Autodesk Fusion 360 part; units mm, degrees
(part 2 of 3)
sketch "Control PCB carrier sketch" plane through (0, 0, 46.5) normal (0, 0, 1) x (1, 0, 0) in component "V2 control PCB removable carrier"
  line L0 (42, 28) -> (98, 28)
  line L1 (100, 30) -> (100, 61)
  line L2 (98, 63) -> (42, 63)
  line L3 (40, 61) -> (40, 30)
  arc A0 (98, 28) -> (100, 30) centre (98, 30) ccw
  arc A1 (100, 61) -> (98, 63) centre (98, 61) ccw
  arc A2 (42, 63) -> (40, 61) centre (42, 61) ccw
  arc A3 (40, 30) -> (42, 28) centre (42, 30) ccw
extrude "Control PCB carrier" add sketch "Control PCB carrier sketch" along normal blind 2.5 separate body makes body 8 in component "V2 control PCB removable carrier"
ref_plane "WorkPlane2" through (0, 0, 46.4) normal (0, 0, 1) x (1, 0, 0) in component "V2 control PCB removable carrier"
sketch "Carrier M3 through sketch" plane through (0, 0, 46.4) normal (0, 0, 1) x (1, 0, 0) in component "V2 control PCB removable carrier"
  circle A0 centre (45, 44) radius 1.7
  circle A1 centre (95, 44) radius 1.7
extrude "Carrier M3 through" cut sketch "Carrier M3 through sketch" along normal blind 2.8 bodies 8 in component "V2 control PCB removable carrier"
ref_plane "WorkPlane3" through (0, 0, 49) normal (0, 0, 1) x (1, 0, 0) in component "V2 control PCB removable carrier"
sketch "Control PCB corner support pads" plane through (0, 0, 49) normal (0, 0, 1) x (1, 0, 0) in component "V2 control PCB removable carrier"
  line L0 (54, 30) -> (57, 30)
  line L1 (57, 30) -> (57, 33)
  line L2 (57, 33) -> (54, 33)
  line L3 (54, 33) -> (54, 30)
  line L4 (54, 57) -> (57, 57)
  line L5 (57, 57) -> (57, 60)
  line L6 (57, 60) -> (54, 60)
  line L7 (54, 60) -> (54, 57)
  line L8 (83, 30) -> (86, 30)
  line L9 (86, 30) -> (86, 33)
  line L10 (86, 33) -> (83, 33)
  line L11 (83, 33) -> (83, 30)
  line L12 (83, 57) -> (86, 57)
  line L13 (86, 57) -> (86, 60)
  line L14 (86, 60) -> (83, 60)
  line L15 (83, 60) -> (83, 57)
extrude "PCB stand-off pads" add sketch "Control PCB corner support pads" along normal blind 4 bodies 8 in component "V2 control PCB removable carrier"
ref_plane "WorkPlane4" through (0, 0, 49) normal (0, 0, 1) x (1, 0, 0) in component "V2 control PCB removable carrier"
sketch "Control PCB guide sketch" plane through (0, 0, 49) normal (0, 0, 1) x (1, 0, 0) in component "V2 control PCB removable carrier"
  line L0 (51.5, 30) -> (53.5, 30)
  line L1 (53.5, 30) -> (53.5, 60)
  line L2 (53.5, 60) -> (51.5, 60)
  line L3 (51.5, 60) -> (51.5, 30)
extrude "Control PCB guide" add sketch "Control PCB guide sketch" along normal blind 5 bodies 8 in component "V2 control PCB removable carrier"
ref_plane "WorkPlane5" through (0, 0, 49) normal (0, 0, 1) x (1, 0, 0) in component "V2 control PCB removable carrier"
sketch "Control PCB guide sketch (1)" plane through (0, 0, 49) normal (0, 0, 1) x (1, 0, 0) in component "V2 control PCB removable carrier"
  line L0 (86.5, 30) -> (88.5, 30)
  line L1 (88.5, 30) -> (88.5, 60)
  line L2 (88.5, 60) -> (86.5, 60)
  line L3 (86.5, 60) -> (86.5, 30)
extrude "Control PCB guide (1)" add sketch "Control PCB guide sketch (1)" along normal blind 5 bodies 8 in component "V2 control PCB removable carrier"
ref_plane "WorkPlane6" through (0, 0, 49) normal (0, 0, 1) x (1, 0, 0) in component "V2 control PCB removable carrier"
sketch "Control PCB guide sketch (2)" plane through (0, 0, 49) normal (0, 0, 1) x (1, 0, 0) in component "V2 control PCB removable carrier"
  line L0 (54, 27.5) -> (86, 27.5)
  line L1 (86, 27.5) -> (86, 29.5)
  line L2 (86, 29.5) -> (54, 29.5)
  line L3 (54, 29.5) -> (54, 27.5)
extrude "Control PCB guide (2)" add sketch "Control PCB guide sketch (2)" along normal blind 5 bodies 8 in component "V2 control PCB removable carrier"
ref_plane "WorkPlane7" through (0, 0, 46.4) normal (0, 0, 1) x (1, 0, 0) in component "V2 control PCB removable carrier"
sketch "PCB retaining strap slot sketch" plane through (0, 0, 46.4) normal (0, 0, 1) x (1, 0, 0) in component "V2 control PCB removable carrier"
  line L0 (52, 48) -> (54, 48)
  line L1 (54, 48) -> (54, 54)
  line L2 (54, 54) -> (52, 54)
  line L3 (52, 54) -> (52, 48)
extrude "PCB retaining strap slot" cut sketch "PCB retaining strap slot sketch" along normal blind 2.8 bodies 8 in component "V2 control PCB removable carrier"
ref_plane "WorkPlane8" through (0, 0, 46.4) normal (0, 0, 1) x (1, 0, 0) in component "V2 control PCB removable carrier"
sketch "PCB retaining strap slot sketch (1)" plane through (0, 0, 46.4) normal (0, 0, 1) x (1, 0, 0) in component "V2 control PCB removable carrier"
  line L0 (85, 48) -> (87, 48)
  line L1 (87, 48) -> (87, 54)
  line L2 (87, 54) -> (85, 54)
  line L3 (85, 54) -> (85, 48)
extrude "PCB retaining strap slot (1)" cut sketch "PCB retaining strap slot sketch (1)" along normal blind 2.8 bodies 8 in component "V2 control PCB removable carrier"
ref_plane "WorkPlane1" through (0, 0, 58.6) normal (0, 0, 1) x (1, 0, 0) in component "V2 captured tactile plunger 1"
sketch "Tactile contact stem" plane through (0, 0, 58.6) normal (0, 0, 1) x (1, 0, 0) in component "V2 captured tactile plunger 1"
  circle A0 centre (62.38, 53) radius 2
extrude "Tactile contact stem (1)" add sketch "Tactile contact stem" along normal blind 8.2 separate body makes body 9 in component "V2 captured tactile plunger 1"
ref_plane "WorkPlane2" through (0, 0, 65.2) normal (0, 0, 1) x (1, 0, 0) in component "V2 captured tactile plunger 1"
sketch "Captive flange" plane through (0, 0, 65.2) normal (0, 0, 1) x (1, 0, 0) in component "V2 captured tactile plunger 1"
  circle A0 centre (62.38, 53) radius 3.5
extrude "Captive flange (1)" add sketch "Captive flange" along normal blind 1.6 bodies 9 in component "V2 captured tactile plunger 1"
ref_plane "WorkPlane3" through (0, 0, 66.8) normal (0, 0, 1) x (1, 0, 0) in component "V2 captured tactile plunger 1"
sketch "Finger tip" plane through (0, 0, 66.8) normal (0, 0, 1) x (1, 0, 0) in component "V2 captured tactile plunger 1"
  circle A0 centre (62.38, 53) radius 2.75
extrude "Finger tip (1)" add sketch "Finger tip" along normal blind 3.6 bodies 9 in component "V2 captured tactile plunger 1"
ref_plane "WorkPlane1" through (0, 0, 58.6) normal (0, 0, 1) x (1, 0, 0) in component "V2 captured tactile plunger 2"
sketch "Tactile contact stem (2)" plane through (0, 0, 58.6) normal (0, 0, 1) x (1, 0, 0) in component "V2 captured tactile plunger 2"
  circle A0 centre (70, 53) radius 2
extrude "Tactile contact stem (1)'" add sketch "Tactile contact stem (2)" along normal blind 8.2 separate body makes body 10 in component "V2 captured tactile plunger 2"
ref_plane "WorkPlane2" through (0, 0, 65.2) normal (0, 0, 1) x (1, 0, 0) in component "V2 captured tactile plunger 2"
sketch "Captive flange (2)" plane through (0, 0, 65.2) normal (0, 0, 1) x (1, 0, 0) in component "V2 captured tactile plunger 2"
  circle A0 centre (70, 53) radius 3.5
extrude "Captive flange (1)'" add sketch "Captive flange (2)" along normal blind 1.6 bodies 10 in component "V2 captured tactile plunger 2"
ref_plane "WorkPlane3" through (0, 0, 66.8) normal (0, 0, 1) x (1, 0, 0) in component "V2 captured tactile plunger 2"
sketch "Finger tip (2)" plane through (0, 0, 66.8) normal (0, 0, 1) x (1, 0, 0) in component "V2 captured tactile plunger 2"
  circle A0 centre (70, 53) radius 2.75
extrude "Finger tip (1)'" add sketch "Finger tip (2)" along normal blind 3.6 bodies 10 in component "V2 captured tactile plunger 2"
ref_plane "WorkPlane1" through (0, 0, 58.6) normal (0, 0, 1) x (1, 0, 0) in component "V2 captured tactile plunger 3"
sketch "Tactile contact stem (3)" plane through (0, 0, 58.6) normal (0, 0, 1) x (1, 0, 0) in component "V2 captured tactile plunger 3"
  circle A0 centre (77.62, 53) radius 2
extrude "Tactile contact stem (1)''" add sketch "Tactile contact stem (3)" along normal blind 8.2 separate body makes body 11 in component "V2 captured tactile plunger 3"
ref_plane "WorkPlane2" through (0, 0, 65.2) normal (0, 0, 1) x (1, 0, 0) in component "V2 captured tactile plunger 3"
sketch "Captive flange (3)" plane through (0, 0, 65.2) normal (0, 0, 1) x (1, 0, 0) in component "V2 captured tactile plunger 3"
  circle A0 centre (77.62, 53) radius 3.5
extrude "Captive flange (1)''" add sketch "Captive flange (3)" along normal blind 1.6 bodies 11 in component "V2 captured tactile plunger 3"
ref_plane "WorkPlane3" through (0, 0, 66.8) normal (0, 0, 1) x (1, 0, 0) in component "V2 captured tactile plunger 3"
sketch "Finger tip (3)" plane through (0, 0, 66.8) normal (0, 0, 1) x (1, 0, 0) in component "V2 captured tactile plunger 3"
  circle A0 centre (77.62, 53) radius 2.75
extrude "Finger tip (1)''" add sketch "Finger tip (3)" along normal blind 3.6 bodies 11 in component "V2 captured tactile plunger 3"
ref_plane "WorkPlane1" through (0, 0, 8) normal (0, 0, 1) x (1, 0, 0) in component "REF main board 90x80x20 - photo estimate"
sketch "Main PCB sketch" plane through (0, 0, 8) normal (0, 0, 1) x (1, 0, 0) in component "REF main board 90x80x20 - photo estimate"
  line L0 (25, 20) -> (115, 20)
  line L1 (115, 20) -> (115, 100)
  line L2 (115, 100) -> (25, 100)
  line L3 (25, 100) -> (25, 20)
extrude "Main PCB" add sketch "Main PCB sketch" along normal blind 1.6 separate body makes body 12 in component "REF main board 90x80x20 - photo estimate"
ref_plane "WorkPlane2" through (0, 0, 9.6) normal (0, 0, 1) x (1, 0, 0) in component "REF main board 90x80x20 - photo estimate"
sketch "ESP32 reference sketch" plane through (0, 0, 9.6) normal (0, 0, 1) x (1, 0, 0) in component "REF main board 90x80x20 - photo estimate"
  line L0 (68, 38) -> (95, 38)
  line L1 (95, 38) -> (95, 88)
  line L2 (95, 88) -> (68, 88)
  line L3 (68, 88) -> (68, 38)
extrude "ESP32 reference" add sketch "ESP32 reference sketch" along normal blind 12 separate body makes body 13 in component "REF main board 90x80x20 - photo estimate"
ref_plane "WorkPlane3" through (0, 0, 9.6) normal (0, 0, 1) x (1, 0, 0) in component "REF main board 90x80x20 - photo estimate"
sketch "nRF24 reference sketch" plane through (0, 0, 9.6) normal (0, 0, 1) x (1, 0, 0) in component "REF main board 90x80x20 - photo estimate"
  line L0 (33, 75) -> (68, 75)
  line L1 (68, 75) -> (68, 93)
  line L2 (68, 93) -> (33, 93)
  line L3 (33, 93) -> (33, 75)
extrude "nRF24 reference" add sketch "nRF24 reference sketch" along normal blind 10 separate body makes body 14 in component "REF main board 90x80x20 - photo estimate"
ref_plane "WorkPlane4" through (0, 0, 9.6) normal (0, 0, 1) x (1, 0, 0) in component "REF main board 90x80x20 - photo estimate"
sketch "MPU6050 reference sketch" plane through (0, 0, 9.6) normal (0, 0, 1) x (1, 0, 0) in component "REF main board 90x80x20 - photo estimate"
  line L0 (36, 34) -> (57, 34)
  line L1 (57, 34) -> (57, 50)
  line L2 (57, 50) -> (36, 50)
  line L3 (36, 50) -> (36, 34)
extrude "MPU6050 reference" add sketch "MPU6050 reference sketch" along normal blind 6 separate body makes body 15 in component "REF main board 90x80x20 - photo estimate"
ref_plane "WorkPlane5" through (0, 0, 9.6) normal (0, 0, 1) x (1, 0, 0) in component "REF main board 90x80x20 - photo estimate"
sketch "Tallest component 20mm total sketch" plane through (0, 0, 9.6) normal (0, 0, 1) x (1, 0, 0) in component "REF main board 90x80x20 - photo estimate"
  line L0 (62, 22) -> (72, 22)
  line L1 (72, 22) -> (72, 32)
  line L2 (72, 32) -> (62, 32)
  line L3 (62, 32) -> (62, 22)
extrude "Tallest component 20mm total" add sketch "Tallest component 20mm total sketch" along normal blind 18.4 separate body makes body 16 in component "REF main board 90x80x20 - photo estimate"
ref_plane "WorkPlane6" through (0, 0, 11) normal (0, 0, 1) x (1, 0, 0) in component "REF main board 90x80x20 - photo estimate"
sketch "Rocker switch side clearance sketch" plane through (0, 0, 11) normal (0, 0, 1) x (1, 0, 0) in component "REF main board 90x80x20 - photo estimate"
  line L0 (18, 23) -> (25, 23)
  line L1 (25, 23) -> (25, 39)
  line L2 (25, 39) -> (18, 39)
  line L3 (18, 39) -> (18, 23)
extrude "Rocker switch side clearance" add sketch "Rocker switch side clearance sketch" along normal blind 12 separate body makes body 17 in component "REF main board 90x80x20 - photo estimate"
ref_plane "WorkPlane7" through (0, 0, 13) normal (0, 0, 1) x (1, 0, 0) in component "REF main board 90x80x20 - photo estimate"
sketch "SMA connector space sketch" plane through (0, 0, 13) normal (0, 0, 1) x (1, 0, 0) in component "REF main board 90x80x20 - photo estimate"
  line L0 (16, 80) -> (25, 80)
  line L1 (25, 80) -> (25, 86)
  line L2 (25, 86) -> (16, 86)
  line L3 (16, 86) -> (16, 80)
extrude "SMA connector space" add sketch "SMA connector space sketch" along normal blind 6 separate body makes body 18 in component "REF main board 90x80x20 - photo estimate"
ref_plane "WorkPlane1" through (0, 0, 53) normal (0, 0, 1) x (1, 0, 0) in component "REF actual combined buttons LEDs PCB - estimated"
sketch "Control PCB estimated 30x30 sketch" plane through (0, 0, 53) normal (0, 0, 1) x (1, 0, 0) in component "REF actual combined buttons LEDs PCB - estimated"
  line L0 (55, 30) -> (85, 30)
  line L1 (85, 30) -> (85, 60)
  line L2 (85, 60) -> (55, 60)
  line L3 (55, 60) -> (55, 30)
extrude "Control PCB estimated 30x30" add sketch "Control PCB estimated 30x30 sketch" along normal blind 1.6 separate body makes body 19 in component "REF actual combined buttons LEDs PCB - estimated"
ref_plane "WorkPlane2" through (0, 0, 54.6) normal (0, 0, 1) x (1, 0, 0) in component "REF actual combined buttons LEDs PCB - estimated"
sketch "Tactile switch 6x6 sketch" plane through (0, 0, 54.6) normal (0, 0, 1) x (1, 0, 0) in component "REF actual combined buttons LEDs PCB - estimated"
  line L0 (59.38, 50) -> (65.38, 50)
  line L1 (65.38, 50) -> (65.38, 56)
  line L2 (65.38, 56) -> (59.38, 56)
  line L3 (59.38, 56) -> (59.38, 50)
extrude "Tactile switch 6x6" add sketch "Tactile switch 6x6 sketch" along normal blind 3.3 separate body makes body 20 in component "REF actual combined buttons LEDs PCB - estimated"
ref_plane "WorkPlane3" through (0, 0, 57.9) normal (0, 0, 1) x (1, 0, 0) in component "REF actual combined buttons LEDs PCB - estimated"
sketch "Switch actuator" plane through (0, 0, 57.9) normal (0, 0, 1) x (1, 0, 0) in component "REF actual combined buttons LEDs PCB - estimated"
  circle A0 centre (62.38, 53) radius 1.65
extrude "Switch actuator (1)" add sketch "Switch actuator" along normal blind 0.5 separate body makes body 21 in component "REF actual combined buttons LEDs PCB - estimated"
ref_plane "WorkPlane4" through (0, 0, 54.6) normal (0, 0, 1) x (1, 0, 0) in component "REF actual combined buttons LEDs PCB - estimated"
sketch "Tactile switch 6x6 sketch (1)" plane through (0, 0, 54.6) normal (0, 0, 1) x (1, 0, 0) in component "REF actual combined buttons LEDs PCB - estimated"
  line L0 (67, 50) -> (73, 50)
  line L1 (73, 50) -> (73, 56)
  line L2 (73, 56) -> (67, 56)
  line L3 (67, 56) -> (67, 50)
extrude "Tactile switch 6x6 (1)" add sketch "Tactile switch 6x6 sketch (1)" along normal blind 3.3 separate body makes body 22 in component "REF actual combined buttons LEDs PCB - estimated"
ref_plane "WorkPlane5" through (0, 0, 57.9) normal (0, 0, 1) x (1, 0, 0) in component "REF actual combined buttons LEDs PCB - estimated"
sketch "Switch actuator (1)" plane through (0, 0, 57.9) normal (0, 0, 1) x (1, 0, 0) in component "REF actual combined buttons LEDs PCB - estimated"
  circle A0 centre (70, 53) radius 1.65
extrude "Switch actuator (2)" add sketch "Switch actuator (1)" along normal blind 0.5 separate body makes body 23 in component "REF actual combined buttons LEDs PCB - estimated"
ref_plane "WorkPlane6" through (0, 0, 54.6) normal (0, 0, 1) x (1, 0, 0) in component "REF actual combined buttons LEDs PCB - estimated"
sketch "Tactile switch 6x6 sketch (2)" plane through (0, 0, 54.6) normal (0, 0, 1) x (1, 0, 0) in component "REF actual combined buttons LEDs PCB - estimated"
  line L0 (74.62, 50) -> (80.62, 50)
  line L1 (80.62, 50) -> (80.62, 56)
  line L2 (80.62, 56) -> (74.62, 56)
  line L3 (74.62, 56) -> (74.62, 50)
extrude "Tactile switch 6x6 (2)" add sketch "Tactile switch 6x6 sketch (2)" along normal blind 3.3 separate body makes body 24 in component "REF actual combined buttons LEDs PCB - estimated"
ref_plane "WorkPlane7" through (0, 0, 57.9) normal (0, 0, 1) x (1, 0, 0) in component "REF actual combined buttons LEDs PCB - estimated"
sketch "Switch actuator (2)" plane through (0, 0, 57.9) normal (0, 0, 1) x (1, 0, 0) in component "REF actual combined buttons LEDs PCB - estimated"
  circle A0 centre (77.62, 53) radius 1.65
extrude "Switch actuator (3)" add sketch "Switch actuator (2)" along normal blind 0.5 separate body makes body 25 in component "REF actual combined buttons LEDs PCB - estimated"
ref_plane "WorkPlane8" through (0, 0, 54.6) normal (0, 0, 1) x (1, 0, 0) in component "REF actual combined buttons LEDs PCB - estimated"
sketch "LED BLUE" plane through (0, 0, 54.6) normal (0, 0, 1) x (1, 0, 0) in component "REF actual combined buttons LEDs PCB - estimated"
  circle A0 centre (63.65, 39) radius 1.5
extrude "LED BLUE (1)" add sketch "LED BLUE" along normal blind 4.5 separate body makes body 26 in component "REF actual combined buttons LEDs PCB - estimated"
ref_plane "WorkPlane9" through (0, 0, 54.6) normal (0, 0, 1) x (1, 0, 0) in component "REF actual combined buttons LEDs PCB - estimated"
sketch "LED RED" plane through (0, 0, 54.6) normal (0, 0, 1) x (1, 0, 0) in component "REF actual combined buttons LEDs PCB - estimated"
  circle A0 centre (70, 39) radius 1.5
extrude "LED RED (1)" add sketch "LED RED" along normal blind 4.5 separate body makes body 27 in component "REF actual combined buttons LEDs PCB - estimated"
ref_plane "WorkPlane10" through (0, 0, 54.6) normal (0, 0, 1) x (1, 0, 0) in component "REF actual combined buttons LEDs PCB - estimated"
sketch "LED GREEN" plane through (0, 0, 54.6) normal (0, 0, 1) x (1, 0, 0) in component "REF actual combined buttons LEDs PCB - estimated"
  circle A0 centre (76.35, 39) radius 1.5
extrude "LED GREEN (1)" add sketch "LED GREEN" along normal blind 4.5 separate body makes body 28 in component "REF actual combined buttons LEDs PCB - estimated"
ref_plane "WorkPlane23" through (0, 0, 14) normal (0, 0, 1) x (1, 0, 0) in component "01 BASE - PCB at bottom"
sketch "V2 repaired rear cable outlet sketch" plane through (0, 0, 14) normal (0, 0, 1) x (1, 0, 0) in component "01 BASE - PCB at bottom"
  line L0 (38, 176.5) -> (62, 176.5)
  line L1 (62, 176.5) -> (62, 180.5)
  line L2 (62, 180.5) -> (38, 180.5)
  line L3 (38, 180.5) -> (38, 176.5)
extrude "V2 repaired rear cable outlet" cut sketch "V2 repaired rear cable outlet sketch" along normal blind 10 bodies 1 in component "01 BASE - PCB at bottom"
ref_plane "WorkPlane24" through (0, 0, 14) normal (0, 0, 1) x (1, 0, 0) in component "01 BASE - PCB at bottom"
sketch "V2 repaired rear cable outlet sketch (1)" plane through (0, 0, 14) normal (0, 0, 1) x (1, 0, 0) in component "01 BASE - PCB at bottom"
  line L0 (78, 176.5) -> (102, 176.5)
  line L1 (102, 176.5) -> (102, 180.5)
  line L2 (102, 180.5) -> (78, 180.5)
  line L3 (78, 180.5) -> (78, 176.5)
extrude "V2 repaired rear cable outlet (1)" cut sketch "V2 repaired rear cable outlet sketch (1)" along normal blind 10 bodies 1 in component "01 BASE - PCB at bottom"
ref_plane "WorkPlane25" through (0, 0, 3) normal (0, 0, 1) x (1, 0, 0) in component "01 BASE - PCB at bottom"
sketch "V2 relocated switch-side clamp pedestal sketch" plane through (0, 0, 3) normal (0, 0, 1) x (1, 0, 0) in component "01 BASE - PCB at bottom"
  circle A0 centre (20, 48) radius 4
extrude "V2 relocated switch-side clamp pedestal" add sketch "V2 relocated switch-side clamp pedestal sketch" along normal blind 6.6 bodies 1 in component "01 BASE - PCB at bottom"
ref_plane "WorkPlane26" through (0, 0, 3) normal (0, 0, 1) x (1, 0, 0) in component "01 BASE - PCB at bottom"
sketch "V2 relocated main PCB support sketch" plane through (0, 0, 3) normal (0, 0, 1) x (1, 0, 0) in component "01 BASE - PCB at bottom"
  line L0 (23, 43) -> (29, 43)
  line L1 (29, 43) -> (29, 53)
  line L2 (29, 53) -> (23, 53)
  line L3 (23, 53) -> (23, 43)
extrude "V2 relocated main PCB support" add sketch "V2 relocated main PCB support sketch" along normal blind 5 bodies 1 in component "01 BASE - PCB at bottom"
ref_plane "WorkPlane27" through (0, 0, 3.1) normal (0, 0, 1) x (1, 0, 0) in component "01 BASE - PCB at bottom"
sketch "V2 relocated clamp pilot sketch" plane through (0, 0, 3.1) normal (0, 0, 1) x (1, 0, 0) in component "01 BASE - PCB at bottom"
  circle A0 centre (20, 48) radius 1.25
extrude "V2 relocated clamp pilot" cut sketch "V2 relocated clamp pilot sketch" along normal blind 6.6 bodies 1 in component "01 BASE - PCB at bottom"
ref_plane "WorkPlane9" through (0, 0, 46.4) normal (0, 0, 1) x (1, 0, 0) in component "V2 control PCB removable carrier"
sketch "V2 front margin retaining strap slot sketch" plane through (0, 0, 46.4) normal (0, 0, 1) x (1, 0, 0) in component "V2 control PCB removable carrier"
  line L0 (52, 31) -> (54, 31)
  line L1 (54, 31) -> (54, 35)
  line L2 (54, 35) -> (52, 35)
  line L3 (52, 35) -> (52, 31)
extrude "V2 front margin retaining strap slot" cut sketch "V2 front margin retaining strap slot sketch" along normal blind 2.8 bodies 8 in component "V2 control PCB removable carrier"
ref_plane "WorkPlane10" through (0, 0, 46.4) normal (0, 0, 1) x (1, 0, 0) in component "V2 control PCB removable carrier"
sketch "V2 front margin retaining strap slot sketch (1)" plane through (0, 0, 46.4) normal (0, 0, 1) x (1, 0, 0) in component "V2 control PCB removable carrier"
  line L0 (85, 31) -> (87, 31)
  line L1 (87, 31) -> (87, 35)
  line L2 (87, 35) -> (85, 35)
  line L3 (85, 35) -> (85, 31)
extrude "V2 front margin retaining strap slot (1)" cut sketch "V2 front margin retaining strap slot sketch (1)" along normal blind 2.8 bodies 8 in component "V2 control PCB removable carrier"
move_body "V2 permanent clamp clearance correction" bodies 3 to x (1, 0, 0) y (0, 1, 0) z (0, 0, 1) at (0, 13, 0) in component "V2 MAIN clamp 1"
ref_plane "WorkPlane33" through (0, 0, 59.9) normal (0, 0, 1) x (1, 0, 0) in component "02 LID - LCD buttons LEDs"
sketch "V3 PETG lip side relief sketch" plane through (0, 0, 59.9) normal (0, 0, 1) x (1, 0, 0) in component "02 LID - LCD buttons LEDs"
  line L0 (3.2, 15.9) -> (3.5, 15.9)
  line L1 (3.5, 15.9) -> (3.5, 164.1)
  line L2 (3.5, 164.1) -> (3.2, 164.1)
  line L3 (3.2, 164.1) -> (3.2, 15.9)
extrude "V3 PETG lip side relief" cut sketch "V3 PETG lip side relief sketch" along normal blind 4.2 bodies 2 in component "02 LID - LCD buttons LEDs"
ref_plane "WorkPlane34" through (0, 0, 59.9) normal (0, 0, 1) x (1, 0, 0) in component "02 LID - LCD buttons LEDs"
sketch "V3 PETG lip side relief sketch (1)" plane through (0, 0, 59.9) normal (0, 0, 1) x (1, 0, 0) in component "02 LID - LCD buttons LEDs"
  line L0 (136.5, 15.9) -> (136.8, 15.9)
  line L1 (136.8, 15.9) -> (136.8, 164.1)
  line L2 (136.8, 164.1) -> (136.5, 164.1)
  line L3 (136.5, 164.1) -> (136.5, 15.9)
extrude "V3 PETG lip side relief (1)" cut sketch "V3 PETG lip side relief sketch (1)" along normal blind 4.2 bodies 2 in component "02 LID - LCD buttons LEDs"
ref_plane "WorkPlane35" through (0, 0, 59.9) normal (0, 0, 1) x (1, 0, 0) in component "02 LID - LCD buttons LEDs"
sketch "V3 PETG lip side relief sketch (2)" plane through (0, 0, 59.9) normal (0, 0, 1) x (1, 0, 0) in component "02 LID - LCD buttons LEDs"
  line L0 (15.9, 3.2) -> (124.1, 3.2)
  line L1 (124.1, 3.2) -> (124.1, 3.5)
  line L2 (124.1, 3.5) -> (15.9, 3.5)
  line L3 (15.9, 3.5) -> (15.9, 3.2)
extrude "V3 PETG lip side relief (2)" cut sketch "V3 PETG lip side relief sketch (2)" along normal blind 4.2 bodies 2 in component "02 LID - LCD buttons LEDs"
ref_plane "WorkPlane36" through (0, 0, 59.9) normal (0, 0, 1) x (1, 0, 0) in component "02 LID - LCD buttons LEDs"
sketch "V3 PETG lip side relief sketch (3)" plane through (0, 0, 59.9) normal (0, 0, 1) x (1, 0, 0) in component "02 LID - LCD buttons LEDs"
  line L0 (15.9, 176.5) -> (124.1, 176.5)
  line L1 (124.1, 176.5) -> (124.1, 176.8)
  line L2 (124.1, 176.8) -> (15.9, 176.8)
  line L3 (15.9, 176.8) -> (15.9, 176.5)
extrude "V3 PETG lip side relief (3)" cut sketch "V3 PETG lip side relief sketch (3)" along normal blind 4.2 bodies 2 in component "02 LID - LCD buttons LEDs"
ref_plane "WorkPlane37" through (0, 0, 63.9) normal (0, 0, 1) x (1, 0, 0) in component "02 LID - LCD buttons LEDs"
sketch "V3 PETG M3 cover clearance sketch" plane through (0, 0, 63.9) normal (0, 0, 1) x (1, 0, 0) in component "02 LID - LCD buttons LEDs"
  circle A0 centre (8, 8) radius 1.8
  circle A1 centre (132, 8) radius 1.8
  circle A2 centre (8, 172) radius 1.8
  circle A3 centre (132, 172) radius 1.8
  dimension "d713" = 3.6
  dimension "d714" = 3.6
  dimension "d715" = 3.6
  dimension "d716" = 3.6
  measures "d713" diameter of A0
  measures "d714" diameter of A1
  measures "d715" diameter of A2
  measures "d716" diameter of A3
extrude "V3 PETG M3 cover clearance" cut sketch "V3 PETG M3 cover clearance sketch" along normal blind 3.3 bodies 2 in component "02 LID - LCD buttons LEDs"
ref_plane "WorkPlane38" through (0, 0, 65.6) normal (0, 0, 1) x (1, 0, 0) in component "02 LID - LCD buttons LEDs"
sketch "V3 M3 cover head recess sketch" plane through (0, 0, 65.6) normal (0, 0, 1) x (1, 0, 0) in component "02 LID - LCD buttons LEDs"
  circle A0 centre (8, 8) radius 3.4
  circle A1 centre (132, 8) radius 3.4
  circle A2 centre (8, 172) radius 3.4
  circle A3 centre (132, 172) radius 3.4
extrude "V3 M3 cover head recess" cut sketch "V3 M3 cover head recess sketch" along normal blind 1.5 bodies 2 in component "02 LID - LCD buttons LEDs"
ref_plane "WorkPlane39" through (0, 0, 51.2) normal (0, 0, 1) x (1, 0, 0) in component "02 LID - LCD buttons LEDs"
sketch "V3 LCD 12.8 mm pillars - filled M3 bores sketch" plane through (0, 0, 51.2) normal (0, 0, 1) x (1, 0, 0) in component "02 LID - LCD buttons LEDs"
  circle A0 centre (23.5, 100.5) radius 3.5
  circle A1 centre (116.5, 100.5) radius 3.5
  circle A2 centre (23.5, 155.5) radius 3.5
  circle A3 centre (116.5, 155.5) radius 3.5
extrude "V3 LCD 12.8 mm pillars - filled M3 bores" add sketch "V3 LCD 12.8 mm pillars - filled M3 bores sketch" along normal blind 12.8 bodies 2 in component "02 LID - LCD buttons LEDs"
ref_plane "WorkPlane40" through (0, 0, 51.1) normal (0, 0, 1) x (1, 0, 0) in component "02 LID - LCD buttons LEDs"
sketch "V3 LCD M2 tapping pilots sketch" plane through (0, 0, 51.1) normal (0, 0, 1) x (1, 0, 0) in component "02 LID - LCD buttons LEDs"
  circle A0 centre (23.5, 100.5) radius 0.85
  circle A1 centre (116.5, 100.5) radius 0.85
  circle A2 centre (23.5, 155.5) radius 0.85
  circle A3 centre (116.5, 155.5) radius 0.85
extrude "V3 LCD M2 tapping pilots" cut sketch "V3 LCD M2 tapping pilots sketch" along normal blind 7.3 bodies 2 in component "02 LID - LCD buttons LEDs"
ref_plane "WorkPlane41" through (0, 0, 63.9) normal (0, 0, 1) x (1, 0, 0) in component "02 LID - LCD buttons LEDs"
sketch "V3 LCD aperture 80x28 sketch" plane through (0, 0, 63.9) normal (0, 0, 1) x (1, 0, 0) in component "02 LID - LCD buttons LEDs"
  line L0 (30, 114) -> (110, 114)
  line L1 (110, 114) -> (110, 142)
  line L2 (110, 142) -> (30, 142)
  line L3 (30, 142) -> (30, 114)
extrude "V3 LCD aperture 80x28" cut sketch "V3 LCD aperture 80x28 sketch" along normal blind 3.3 bodies 2 in component "02 LID - LCD buttons LEDs"
ref_plane "WorkPlane28" through (0, 0, 3) normal (0, 0, 1) x (1, 0, 0) in component "01 BASE - PCB at bottom"
sketch "V3 clear old relay mounts sketch" plane through (0, 0, 3) normal (0, 0, 1) x (1, 0, 0) in component "01 BASE - PCB at bottom"
  line L0 (22, 111) -> (118, 111)
  line L1 (118, 111) -> (118, 176)
  line L2 (118, 176) -> (22, 176)
  line L3 (22, 176) -> (22, 111)
extrude "V3 clear old relay mounts" cut sketch "V3 clear old relay mounts sketch" along normal blind 30 bodies 1 in component "01 BASE - PCB at bottom"
ref_plane "WorkPlane3" through (0, 0, 9.5) normal (0, 0, 1) x (1, 0, 0) in component "V2 MAIN clamp 1"
sketch "V3 main clamp PETG slot" plane through (0, 0, 9.5) normal (0, 0, 1) x (1, 0, 0) in component "V2 MAIN clamp 1"
  line L0 (18.2, 46.2) -> (21.8, 46.2)
  line L1 (23.5, 47.9) -> (23.5, 48.1)
  line L2 (21.8, 49.8) -> (18.2, 49.8)
  line L3 (16.5, 48.1) -> (16.5, 47.9)
  arc A0 (21.8, 46.2) -> (23.5, 47.9) centre (21.8, 47.9) ccw
  arc A1 (23.5, 48.1) -> (21.8, 49.8) centre (21.8, 48.1) ccw
  arc A2 (18.2, 49.8) -> (16.5, 48.1) centre (18.2, 48.1) ccw
  arc A3 (16.5, 47.9) -> (18.2, 46.2) centre (18.2, 47.9) ccw
extrude "V3 main clamp M3 running clearance" cut sketch "V3 main clamp PETG slot" along normal blind 2.8 bodies 3 in component "V2 MAIN clamp 1"
ref_plane "WorkPlane3" through (0, 0, 9.5) normal (0, 0, 1) x (1, 0, 0) in component "V2 MAIN clamp 2"
sketch "V3 main clamp PETG slot (2)" plane through (0, 0, 9.5) normal (0, 0, 1) x (1, 0, 0) in component "V2 MAIN clamp 2"
  line L0 (118.2, 33.2) -> (121.8, 33.2)
  line L1 (123.5, 34.9) -> (123.5, 35.1)
  line L2 (121.8, 36.8) -> (118.2, 36.8)
  line L3 (116.5, 35.1) -> (116.5, 34.9)
  arc A0 (121.8, 33.2) -> (123.5, 34.9) centre (121.8, 34.9) ccw
  arc A1 (123.5, 35.1) -> (121.8, 36.8) centre (121.8, 35.1) ccw
  arc A2 (118.2, 36.8) -> (116.5, 35.1) centre (118.2, 35.1) ccw
  arc A3 (116.5, 34.9) -> (118.2, 33.2) centre (118.2, 34.9) ccw
extrude "V3 main clamp M3 running clearance'" cut sketch "V3 main clamp PETG slot (2)" along normal blind 2.8 bodies 4 in component "V2 MAIN clamp 2"
ref_plane "WorkPlane3" through (0, 0, 9.5) normal (0, 0, 1) x (1, 0, 0) in component "V2 MAIN clamp 3"
sketch "V3 main clamp PETG slot (3)" plane through (0, 0, 9.5) normal (0, 0, 1) x (1, 0, 0) in component "V2 MAIN clamp 3"
  line L0 (18.2, 83.2) -> (21.8, 83.2)
  line L1 (23.5, 84.9) -> (23.5, 85.1)
  line L2 (21.8, 86.8) -> (18.2, 86.8)
  line L3 (16.5, 85.1) -> (16.5, 84.9)
  arc A0 (21.8, 83.2) -> (23.5, 84.9) centre (21.8, 84.9) ccw
  arc A1 (23.5, 85.1) -> (21.8, 86.8) centre (21.8, 85.1) ccw
  arc A2 (18.2, 86.8) -> (16.5, 85.1) centre (18.2, 85.1) ccw
  arc A3 (16.5, 84.9) -> (18.2, 83.2) centre (18.2, 84.9) ccw
extrude "V3 main clamp M3 running clearance''" cut sketch "V3 main clamp PETG slot (3)" along normal blind 2.8 bodies 5 in component "V2 MAIN clamp 3"
ref_plane "WorkPlane3" through (0, 0, 9.5) normal (0, 0, 1) x (1, 0, 0) in component "V2 MAIN clamp 4"
sketch "V3 main clamp PETG slot (4)" plane through (0, 0, 9.5) normal (0, 0, 1) x (1, 0, 0) in component "V2 MAIN clamp 4"
  line L0 (118.2, 83.2) -> (121.8, 83.2)
  line L1 (123.5, 84.9) -> (123.5, 85.1)
  line L2 (121.8, 86.8) -> (118.2, 86.8)
  line L3 (116.5, 85.1) -> (116.5, 84.9)
  arc A0 (121.8, 83.2) -> (123.5, 84.9) centre (121.8, 84.9) ccw
  arc A1 (123.5, 85.1) -> (121.8, 86.8) centre (121.8, 85.1) ccw
  arc A2 (118.2, 86.8) -> (116.5, 85.1) centre (118.2, 85.1) ccw
  arc A3 (116.5, 84.9) -> (118.2, 83.2) centre (118.2, 84.9) ccw
extrude "V3 main clamp M3 running clearance'''" cut sketch "V3 main clamp PETG slot (4)" along normal blind 2.8 bodies 6 in component "V2 MAIN clamp 4"
ref_plane "WorkPlane29" through (0, 0, 3) normal (0, 0, 1) x (1, 0, 0) in component "01 BASE - PCB at bottom"
sketch "V3 relay edge support sketch" plane through (0, 0, 3) normal (0, 0, 1) x (1, 0, 0) in component "01 BASE - PCB at bottom"
  line L0 (30.25, 117) -> (36.25, 117)
  line L1 (36.25, 117) -> (36.25, 127)
  line L2 (36.25, 127) -> (30.25, 127)
  line L3 (30.25, 127) -> (30.25, 117)
extrude "V3 relay edge support" add sketch "V3 relay edge support sketch" along normal blind 5 bodies 1 in component "01 BASE - PCB at bottom"
ref_plane "WorkPlane30" through (0, 0, 3) normal (0, 0, 1) x (1, 0, 0) in component "01 BASE - PCB at bottom"
sketch "V3 relay edge support sketch (1)" plane through (0, 0, 3) normal (0, 0, 1) x (1, 0, 0) in component "01 BASE - PCB at bottom"
  line L0 (30.25, 155) -> (36.25, 155)
  line L1 (36.25, 155) -> (36.25, 165)
  line L2 (36.25, 165) -> (30.25, 165)
  line L3 (30.25, 165) -> (30.25, 155)
extrude "V3 relay edge support (1)" add sketch "V3 relay edge support sketch (1)" along normal blind 5 bodies 1 in component "01 BASE - PCB at bottom"
ref_plane "WorkPlane31" through (0, 0, 3) normal (0, 0, 1) x (1, 0, 0) in component "01 BASE - PCB at bottom"
sketch "V3 relay edge support sketch (2)" plane through (0, 0, 3) normal (0, 0, 1) x (1, 0, 0) in component "01 BASE - PCB at bottom"
  line L0 (103.75, 117) -> (109.75, 117)
  line L1 (109.75, 117) -> (109.75, 127)
  line L2 (109.75, 127) -> (103.75, 127)
  line L3 (103.75, 127) -> (103.75, 117)
extrude "V3 relay edge support (2)" add sketch "V3 relay edge support sketch (2)" along normal blind 5 bodies 1 in component "01 BASE - PCB at bottom"
ref_plane "WorkPlane32" through (0, 0, 3) normal (0, 0, 1) x (1, 0, 0) in component "01 BASE - PCB at bottom"
sketch "V3 relay edge support sketch (3)" plane through (0, 0, 3) normal (0, 0, 1) x (1, 0, 0) in component "01 BASE - PCB at bottom"
  line L0 (103.75, 155) -> (109.75, 155)
  line L1 (109.75, 155) -> (109.75, 165)
  line L2 (109.75, 165) -> (103.75, 165)
  line L3 (103.75, 165) -> (103.75, 155)
extrude "V3 relay edge support (3)" add sketch "V3 relay edge support sketch (3)" along normal blind 5 bodies 1 in component "01 BASE - PCB at bottom"
ref_plane "WorkPlane33" through (0, 0, 3) normal (0, 0, 1) x (1, 0, 0) in component "01 BASE - PCB at bottom"
sketch "V3 relay clamp pedestals sketch" plane through (0, 0, 3) normal (0, 0, 1) x (1, 0, 0) in component "01 BASE - PCB at bottom"
  circle A0 centre (27.25, 122) radius 4
  circle A1 centre (112.75, 122) radius 4
  circle A2 centre (27.25, 160) radius 4
  circle A3 centre (112.75, 160) radius 4
extrude "V3 relay clamp pedestals" add sketch "V3 relay clamp pedestals sketch" along normal blind 6.6 bodies 1 in component "01 BASE - PCB at bottom"
ref_plane "WorkPlane34" through (0, 0, 3.1) normal (0, 0, 1) x (1, 0, 0) in component "01 BASE - PCB at bottom"
sketch "V3 relay clamp pilots sketch" plane through (0, 0, 3.1) normal (0, 0, 1) x (1, 0, 0) in component "01 BASE - PCB at bottom"
  circle A0 centre (27.25, 122) radius 1.25
  circle A1 centre (112.75, 122) radius 1.25
  circle A2 centre (27.25, 160) radius 1.25
  circle A3 centre (112.75, 160) radius 1.25
extrude "V3 relay clamp pilots" cut sketch "V3 relay clamp pilots sketch" along normal blind 6.6 bodies 1 in component "01 BASE - PCB at bottom"
ref_plane "WorkPlane1" through (0, 0, 9.6) normal (0, 0, 1) x (1, 0, 0) in component "V3 RELAY adjustable clamp 1"
sketch "V3 relay clamp sketch" plane through (0, 0, 9.6) normal (0, 0, 1) x (1, 0, 0) in component "V3 RELAY adjustable clamp 1"
  line L0 (23.25, 117) -> (35.25, 117)
  line L1 (36.25, 118) -> (36.25, 126)
  line L2 (35.25, 127) -> (23.25, 127)
  line L3 (22.25, 126) -> (22.25, 118)
  arc A0 (35.25, 117) -> (36.25, 118) centre (35.25, 118) ccw
  arc A1 (36.25, 126) -> (35.25, 127) centre (35.25, 126) ccw
  arc A2 (23.25, 127) -> (22.25, 126) centre (23.25, 126) ccw
  arc A3 (22.25, 118) -> (23.25, 117) centre (23.25, 118) ccw
extrude "V3 relay clamp" add sketch "V3 relay clamp sketch" along normal blind 3 separate body makes body 29 in component "V3 RELAY adjustable clamp 1"
ref_plane "WorkPlane2" through (0, 0, 9.5) normal (0, 0, 1) x (1, 0, 0) in component "V3 RELAY adjustable clamp 1"
sketch "V3 8 mm adjustment slot" plane through (0, 0, 9.5) normal (0, 0, 1) x (1, 0, 0) in component "V3 RELAY adjustable clamp 1"
  line L0 (24.95, 120.2) -> (29.55, 120.2)
  line L1 (31.25, 121.9) -> (31.25, 122.1)
  line L2 (29.55, 123.8) -> (24.95, 123.8)
  line L3 (23.25, 122.1) -> (23.25, 121.9)
  arc A0 (29.55, 120.2) -> (31.25, 121.9) centre (29.55, 121.9) ccw
  arc A1 (31.25, 122.1) -> (29.55, 123.8) centre (29.55, 122.1) ccw
  arc A2 (24.95, 123.8) -> (23.25, 122.1) centre (24.95, 122.1) ccw
  arc A3 (23.25, 121.9) -> (24.95, 120.2) centre (24.95, 121.9) ccw
extrude "V3 adjustable M3 clamp slot" cut sketch "V3 8 mm adjustment slot" along normal blind 3.3 bodies 29 in component "V3 RELAY adjustable clamp 1"
ref_plane "WorkPlane1" through (0, 0, 9.6) normal (0, 0, 1) x (1, 0, 0) in component "V3 RELAY adjustable clamp 2"
sketch "V3 relay clamp sketch (2)" plane through (0, 0, 9.6) normal (0, 0, 1) x (1, 0, 0) in component "V3 RELAY adjustable clamp 2"
  line L0 (104.75, 117) -> (116.75, 117)
  line L1 (117.75, 118) -> (117.75, 126)
  line L2 (116.75, 127) -> (104.75, 127)
  line L3 (103.75, 126) -> (103.75, 118)
  arc A0 (116.75, 117) -> (117.75, 118) centre (116.75, 118) ccw
  arc A1 (117.75, 126) -> (116.75, 127) centre (116.75, 126) ccw
  arc A2 (104.75, 127) -> (103.75, 126) centre (104.75, 126) ccw
  arc A3 (103.75, 118) -> (104.75, 117) centre (104.75, 118) ccw
extrude "V3 relay clamp'" add sketch "V3 relay clamp sketch (2)" along normal blind 3 separate body makes body 30 in component "V3 RELAY adjustable clamp 2"
ref_plane "WorkPlane2" through (0, 0, 9.5) normal (0, 0, 1) x (1, 0, 0) in component "V3 RELAY adjustable clamp 2"
sketch "V3 8 mm adjustment slot (2)" plane through (0, 0, 9.5) normal (0, 0, 1) x (1, 0, 0) in component "V3 RELAY adjustable clamp 2"
  line L0 (110.45, 120.2) -> (115.05, 120.2)
  line L1 (116.75, 121.9) -> (116.75, 122.1)
  line L2 (115.05, 123.8) -> (110.45, 123.8)
  line L3 (108.75, 122.1) -> (108.75, 121.9)
  arc A0 (115.05, 120.2) -> (116.75, 121.9) centre (115.05, 121.9) ccw
  arc A1 (116.75, 122.1) -> (115.05, 123.8) centre (115.05, 122.1) ccw
  arc A2 (110.45, 123.8) -> (108.75, 122.1) centre (110.45, 122.1) ccw
  arc A3 (108.75, 121.9) -> (110.45, 120.2) centre (110.45, 121.9) ccw
extrude "V3 adjustable M3 clamp slot'" cut sketch "V3 8 mm adjustment slot (2)" along normal blind 3.3 bodies 30 in component "V3 RELAY adjustable clamp 2"
ref_plane "WorkPlane1" through (0, 0, 9.6) normal (0, 0, 1) x (1, 0, 0) in component "V3 RELAY adjustable clamp 3"
sketch "V3 relay clamp sketch (3)" plane through (0, 0, 9.6) normal (0, 0, 1) x (1, 0, 0) in component "V3 RELAY adjustable clamp 3"
  line L0 (23.25, 155) -> (35.25, 155)
  line L1 (36.25, 156) -> (36.25, 164)
  line L2 (35.25, 165) -> (23.25, 165)
  line L3 (22.25, 164) -> (22.25, 156)
  arc A0 (35.25, 155) -> (36.25, 156) centre (35.25, 156) ccw
  arc A1 (36.25, 164) -> (35.25, 165) centre (35.25, 164) ccw
  arc A2 (23.25, 165) -> (22.25, 164) centre (23.25, 164) ccw
  arc A3 (22.25, 156) -> (23.25, 155) centre (23.25, 156) ccw
extrude "V3 relay clamp''" add sketch "V3 relay clamp sketch (3)" along normal blind 3 separate body makes body 31 in component "V3 RELAY adjustable clamp 3"
ref_plane "WorkPlane2" through (0, 0, 9.5) normal (0, 0, 1) x (1, 0, 0) in component "V3 RELAY adjustable clamp 3"
sketch "V3 8 mm adjustment slot (3)" plane through (0, 0, 9.5) normal (0, 0, 1) x (1, 0, 0) in component "V3 RELAY adjustable clamp 3"
  line L0 (24.95, 158.2) -> (29.55, 158.2)
  line L1 (31.25, 159.9) -> (31.25, 160.1)
  line L2 (29.55, 161.8) -> (24.95, 161.8)
  line L3 (23.25, 160.1) -> (23.25, 159.9)
  arc A0 (29.55, 158.2) -> (31.25, 159.9) centre (29.55, 159.9) ccw
  arc A1 (31.25, 160.1) -> (29.55, 161.8) centre (29.55, 160.1) ccw
  arc A2 (24.95, 161.8) -> (23.25, 160.1) centre (24.95, 160.1) ccw
  arc A3 (23.25, 159.9) -> (24.95, 158.2) centre (24.95, 159.9) ccw
extrude "V3 adjustable M3 clamp slot''" cut sketch "V3 8 mm adjustment slot (3)" along normal blind 3.3 bodies 31 in component "V3 RELAY adjustable clamp 3"
ref_plane "WorkPlane1" through (0, 0, 9.6) normal (0, 0, 1) x (1, 0, 0) in component "V3 RELAY adjustable clamp 4"
sketch "V3 relay clamp sketch (4)" plane through (0, 0, 9.6) normal (0, 0, 1) x (1, 0, 0) in component "V3 RELAY adjustable clamp 4"
  line L0 (104.75, 155) -> (116.75, 155)
  line L1 (117.75, 156) -> (117.75, 164)
  line L2 (116.75, 165) -> (104.75, 165)
  line L3 (103.75, 164) -> (103.75, 156)
  arc A0 (116.75, 155) -> (117.75, 156) centre (116.75, 156) ccw
  arc A1 (117.75, 164) -> (116.75, 165) centre (116.75, 164) ccw
  arc A2 (104.75, 165) -> (103.75, 164) centre (104.75, 164) ccw
  arc A3 (103.75, 156) -> (104.75, 155) centre (104.75, 156) ccw
extrude "V3 relay clamp'''" add sketch "V3 relay clamp sketch (4)" along normal blind 3 separate body makes body 32 in component "V3 RELAY adjustable clamp 4"
ref_plane "WorkPlane2" through (0, 0, 9.5) normal (0, 0, 1) x (1, 0, 0) in component "V3 RELAY adjustable clamp 4"
sketch "V3 8 mm adjustment slot (4)" plane through (0, 0, 9.5) normal (0, 0, 1) x (1, 0, 0) in component "V3 RELAY adjustable clamp 4"
  line L0 (110.45, 158.2) -> (115.05, 158.2)
  line L1 (116.75, 159.9) -> (116.75, 160.1)
  line L2 (115.05, 161.8) -> (110.45, 161.8)
  line L3 (108.75, 160.1) -> (108.75, 159.9)
  arc A0 (115.05, 158.2) -> (116.75, 159.9) centre (115.05, 159.9) ccw
  arc A1 (116.75, 160.1) -> (115.05, 161.8) centre (115.05, 160.1) ccw
  arc A2 (110.45, 161.8) -> (108.75, 160.1) centre (110.45, 160.1) ccw
  arc A3 (108.75, 159.9) -> (110.45, 158.2) centre (110.45, 159.9) ccw
extrude "V3 adjustable M3 clamp slot'''" cut sketch "V3 8 mm adjustment slot (4)" along normal blind 3.3 bodies 32 in component "V3 RELAY adjustable clamp 4"
ref_plane "WorkPlane35" through (0, 0, 3) normal (0, 0, 1) x (1, 0, 0) in component "01 BASE - PCB at bottom"
sketch "V3 cable tie anchor sketch" plane through (0, 0, 3) normal (0, 0, 1) x (1, 0, 0) in component "01 BASE - PCB at bottom"
  line L0 (37, 170) -> (44, 170)
  line L1 (44, 170) -> (44, 175)
  line L2 (44, 175) -> (37, 175)
  line L3 (37, 175) -> (37, 170)
extrude "V3 cable tie anchor" add sketch "V3 cable tie anchor sketch" along normal blind 8 bodies 1 in component "01 BASE - PCB at bottom"
ref_plane "WorkPlane36" through (0, 0, 5) normal (0, 0, 1) x (1, 0, 0) in component "01 BASE - PCB at bottom"
sketch "V3 cable tie tunnel sketch" plane through (0, 0, 5) normal (0, 0, 1) x (1, 0, 0) in component "01 BASE - PCB at bottom"
  line L0 (38.5, 169.9) -> (42.5, 169.9)
  line L1 (42.5, 169.9) -> (42.5, 175.1)
  line L2 (42.5, 175.1) -> (38.5, 175.1)
  line L3 (38.5, 175.1) -> (38.5, 169.9)
extrude "V3 cable tie tunnel" cut sketch "V3 cable tie tunnel sketch" along normal blind 3 bodies 1 in component "01 BASE - PCB at bottom"
ref_plane "WorkPlane37" through (0, 0, 3) normal (0, 0, 1) x (1, 0, 0) in component "01 BASE - PCB at bottom"
sketch "V3 cable tie anchor sketch (1)" plane through (0, 0, 3) normal (0, 0, 1) x (1, 0, 0) in component "01 BASE - PCB at bottom"
  line L0 (99, 170) -> (106, 170)
  line L1 (106, 170) -> (106, 175)
  line L2 (106, 175) -> (99, 175)
  line L3 (99, 175) -> (99, 170)
extrude "V3 cable tie anchor (1)" add sketch "V3 cable tie anchor sketch (1)" along normal blind 8 bodies 1 in component "01 BASE - PCB at bottom"
ref_plane "WorkPlane38" through (0, 0, 5) normal (0, 0, 1) x (1, 0, 0) in component "01 BASE - PCB at bottom"
sketch "V3 cable tie tunnel sketch (1)" plane through (0, 0, 5) normal (0, 0, 1) x (1, 0, 0) in component "01 BASE - PCB at bottom"
  line L0 (100.5, 169.9) -> (104.5, 169.9)
  line L1 (104.5, 169.9) -> (104.5, 175.1)
  line L2 (104.5, 175.1) -> (100.5, 175.1)
  line L3 (100.5, 175.1) -> (100.5, 169.9)
extrude "V3 cable tie tunnel (1)" cut sketch "V3 cable tie tunnel sketch (1)" along normal blind 3 bodies 1 in component "01 BASE - PCB at bottom"
ref_plane "WorkPlane10" through (0, 0, 66.9) normal (0, 0, 1) x (1, 0, 0) in component "V2 removable control fascia"
sketch "V3 PETG plunger running clearance sketch" plane through (0, 0, 66.9) normal (0, 0, 1) x (1, 0, 0) in component "V2 removable control fascia"
  circle A0 centre (62.38, 53) radius 3.15
  circle A1 centre (70, 53) radius 3.15
  circle A2 centre (77.62, 53) radius 3.15
  dimension "d829" = 6.3
  dimension "d830" = 6.3
  dimension "d831" = 6.3
  measures "d829" diameter of A0
  measures "d830" diameter of A1
  measures "d831" diameter of A2
extrude "V3 PETG plunger running clearance" cut sketch "V3 PETG plunger running clearance sketch" along normal blind 2.8 bodies 7 in component "V2 removable control fascia"
ref_plane "WorkPlane11" through (0, 0, 66.9) normal (0, 0, 1) x (1, 0, 0) in component "V2 removable control fascia"
sketch "V3 fascia M3 clearance sketch" plane through (0, 0, 66.9) normal (0, 0, 1) x (1, 0, 0) in component "V2 removable control fascia"
  circle A0 centre (43, 32) radius 1.8
  circle A1 centre (97, 32) radius 1.8
  circle A2 centre (43, 62) radius 1.8
  circle A3 centre (97, 62) radius 1.8
  dimension "d836" = 3.6
  dimension "d837" = 3.6
  dimension "d838" = 3.6
  dimension "d839" = 3.6
  measures "d836" diameter of A0
  measures "d837" diameter of A1
  measures "d838" diameter of A2
  measures "d839" diameter of A3
extrude "V3 fascia M3 clearance" cut sketch "V3 fascia M3 clearance sketch" along normal blind 2.8 bodies 7 in component "V2 removable control fascia"
ref_plane "WorkPlane11" through (0, 0, 46.4) normal (0, 0, 1) x (1, 0, 0) in component "V2 control PCB removable carrier"
sketch "V3 carrier M3 clearance sketch" plane through (0, 0, 46.4) normal (0, 0, 1) x (1, 0, 0) in component "V2 control PCB removable carrier"
  circle A0 centre (45, 44) radius 1.8
  circle A1 centre (95, 44) radius 1.8
  dimension "d844" = 3.6
  dimension "d845" = 3.6
  measures "d844" diameter of A0
  measures "d845" diameter of A1
extrude "V3 carrier M3 clearance" cut sketch "V3 carrier M3 clearance sketch" along normal blind 2.8 bodies 8 in component "V2 control PCB removable carrier"
ref_plane "WorkPlane11" through (0, 0, 58.3) normal (0, 0, 1) x (1, 0, 0) in component "REF actual combined buttons LEDs PCB - estimated"
sketch "V3 switch 4.3 mm actuator extension" plane through (0, 0, 58.3) normal (0, 0, 1) x (1, 0, 0) in component "REF actual combined buttons LEDs PCB - estimated"
  circle A0 centre (62.38, 53) radius 1.65
extrude "V3 switch 4.3 mm actuator extension (1)" add sketch "V3 switch 4.3 mm actuator extension" along normal blind 0.6 bodies 21 in component "REF actual combined buttons LEDs PCB - estimated"
ref_plane "WorkPlane12" through (0, 0, 58.3) normal (0, 0, 1) x (1, 0, 0) in component "REF actual combined buttons LEDs PCB - estimated"
sketch "V3 switch 4.3 mm actuator extension (1)" plane through (0, 0, 58.3) normal (0, 0, 1) x (1, 0, 0) in component "REF actual combined buttons LEDs PCB - estimated"
  circle A0 centre (70, 53) radius 1.65
extrude "V3 switch 4.3 mm actuator extension (2)" add sketch "V3 switch 4.3 mm actuator extension (1)" along normal blind 0.6 bodies 23 in component "REF actual combined buttons LEDs PCB - estimated"
ref_plane "WorkPlane13" through (0, 0, 58.3) normal (0, 0, 1) x (1, 0, 0) in component "REF actual combined buttons LEDs PCB - estimated"
sketch "V3 switch 4.3 mm actuator extension (2)" plane through (0, 0, 58.3) normal (0, 0, 1) x (1, 0, 0) in component "REF actual combined buttons LEDs PCB - estimated"
  circle A0 centre (77.62, 53) radius 1.65
extrude "V3 switch 4.3 mm actuator extension (3)" add sketch "V3 switch 4.3 mm actuator extension (2)" along normal blind 0.6 bodies 25 in component "REF actual combined buttons LEDs PCB - estimated"
ref_plane "WorkPlane4" through (0, 0, 58.4) normal (0, 0, 1) x (1, 0, 0) in component "V2 captured tactile plunger 1"
sketch "V3 0.35 mm idle button clearance sketch" plane through (0, 0, 58.4) normal (0, 0, 1) x (1, 0, 0) in component "V2 captured tactile plunger 1"
  line L0 (58.38, 49) -> (66.38, 49)
  line L1 (66.38, 49) -> (66.38, 57)
  line L2 (66.38, 57) -> (58.38, 57)
  line L3 (58.38, 57) -> (58.38, 49)
extrude "V3 0.35 mm idle button clearance" cut sketch "V3 0.35 mm idle button clearance sketch" along normal blind 0.85 bodies 9 in component "V2 captured tactile plunger 1"
ref_plane "WorkPlane4" through (0, 0, 58.4) normal (0, 0, 1) x (1, 0, 0) in component "V2 captured tactile plunger 2"
sketch "V3 0.35 mm idle button clearance sketch (2)" plane through (0, 0, 58.4) normal (0, 0, 1) x (1, 0, 0) in component "V2 captured tactile plunger 2"
  line L0 (66, 49) -> (74, 49)
  line L1 (74, 49) -> (74, 57)
  line L2 (74, 57) -> (66, 57)
  line L3 (66, 57) -> (66, 49)
extrude "V3 0.35 mm idle button clearance'" cut sketch "V3 0.35 mm idle button clearance sketch (2)" along normal blind 0.85 bodies 10 in component "V2 captured tactile plunger 2"
ref_plane "WorkPlane4" through (0, 0, 58.4) normal (0, 0, 1) x (1, 0, 0) in component "V2 captured tactile plunger 3"
sketch "V3 0.35 mm idle button clearance sketch (3)" plane through (0, 0, 58.4) normal (0, 0, 1) x (1, 0, 0) in component "V2 captured tactile plunger 3"
  line L0 (73.62, 49) -> (81.62, 49)
  line L1 (81.62, 49) -> (81.62, 57)
  line L2 (81.62, 57) -> (73.62, 57)
  line L3 (73.62, 57) -> (73.62, 49)
extrude "V3 0.35 mm idle button clearance''" cut sketch "V3 0.35 mm idle button clearance sketch (3)" along normal blind 0.85 bodies 11 in component "V2 captured tactile plunger 3"
ref_plane "WorkPlane42" through (0, 0, 67) normal (0, 0, 1) x (1, 0, 0) in component "02 LID - LCD buttons LEDs"
sketch "V3 label H2 PRO" plane through (0, 0, 67) normal (0, 0, 1) x (1, 0, 0) in component "02 LID - LCD buttons LEDs"
  line L0 (20, 159) -> (120, 159) construction
  line L1 (120, 159) -> (120, 173) construction
  line L2 (120, 173) -> (20, 173) construction
  line L3 (20, 173) -> (20, 159) construction
  dimension "d874" = 7
  dimension "d875" = 0
  text T0 "H2 PRO" font "Arial" height 7 align centre middle in box 100 x 14 at (20, 159) x (1, 0) y (0, 1) spacing 1 kerned
extrude "V3 engraving H2 PRO" cut sketch "V3 label H2 PRO" against normal blind 0.6 text T0 bodies 2 in component "02 LID - LCD buttons LEDs"
ref_plane "WorkPlane43" through (0, 0, 67) normal (0, 0, 1) x (1, 0, 0) in component "02 LID - LCD buttons LEDs"